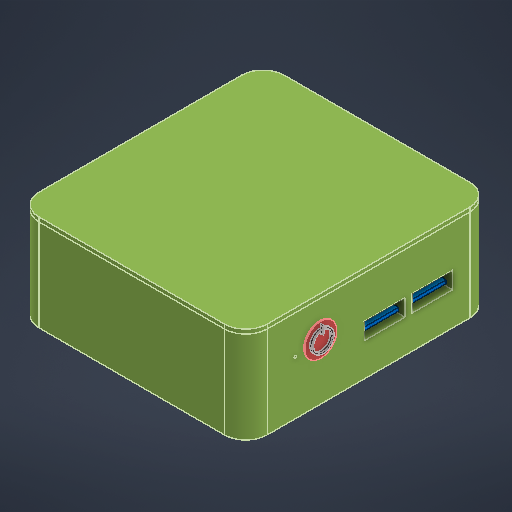
# Autodesk Inventor part: PC
Saved by Autodesk Inventor 2027.1 (Build 311270010, 270A)
## iProperties
Created: 2026-10-10
Part Number: PC
Material: PC/ABS 플라스틱
Document SubType Name: Modeling
Designer: work
Density: 1.1 g/cm^3
Appearance: 올리브 녹색
Author: work
Autodesk Inventor part; units mm, degrees
ref_plane "YZ Plane" through (0, 0, 0) normal (1, 0, 0) x (0, 1, 0)
ref_plane "XZ Plane" through (0, 0, 0) normal (0, 1, 0) x (-1, 0, 0)
sketch "스케치1" plane through (0, 0, 0) normal (0, 1, 0) x (-1, 0, 0)
  line L0 (0, 0) -> (107, 0)
  line L1 (107, 0) -> (107, -115)
  line L2 (107, -115) -> (0, -115)
  line L3 (0, -115) -> (0, 0)
  dimension "d0" = 107
  dimension "d1" = 115
  constraints: 8 end point, 2 parallel, 1 horizontal, 1 perpendicular
  measures "d0" distance of L1.end L2.end
  measures "d1" distance of L0.end L1.end
extrude "돌출1" add sketch "스케치1" along normal blind 45
fillet "모깎기1" radius 10 4 edges at (-107, 22.5, 0) (0, 22.5, 0) (0, 22.5, -115) (-107, 22.5, -115)
sketch "스케치2" plane through (0, 0, -10) normal (1, 0, 0) x (0, 0, -1)
  circle A0 centre (24.6249, 26.5813) radius 7.5
  line L0 (45.4553, 23.4003) -> (86.8672, 23.4003)
  line L1 (86.8672, 23.4003) -> (86.8672, 15.5256)
  line L2 (86.8672, 15.5256) -> (45.4553, 15.5256)
  line L3 (45.4553, 15.5256) -> (45.4553, 23.4003)
  line L4 (64.5413, 23.4003) -> (67.7812, 23.4003)
  line L5 (67.7812, 23.4003) -> (67.7812, 15.5256)
  line L6 (67.7812, 15.5256) -> (64.5413, 15.5256)
  line L7 (64.5413, 15.5256) -> (64.5413, 23.4003)
  point P0 (-10, 0)
  point P1 (66.1613, 23.4003)
  dimension "d5" = 15
  constraints: 16 end point, 4 parallel, 2 horizontal, 2 midpoint, 2 perpendicular, 2 point on line, 1 centre point
  measures "d5" diameter of A0
extrude "돌출2" add sketch "스케치2" along normal blind 0.5 separate body contours A0
extrude "돌출3" cut sketch "스케치2" against normal blind 20 contours L0 L7 L2 L3 | L0 L1 L2 L5 bodies 1
sketch "스케치3" plane through (-20, 0, -10) normal (1, 0, 0) x (0, 0, -1)
  line L0 (64.5413, 15.5256) -> (45.4553, 15.5256) projected
  line L1 (64.5413, 23.4003) -> (64.5413, 15.5256) projected
  line L2 (45.4553, 23.4003) -> (64.5413, 23.4003) projected
  line L3 (45.4553, 15.5256) -> (45.4553, 23.4003) projected
  line L4 (67.7812, 23.4003) -> (86.8672, 23.4003) projected
  line L5 (67.7812, 15.5256) -> (67.7812, 23.4003) projected
  line L6 (86.8672, 15.5256) -> (67.7812, 15.5256) projected
  line L7 (86.8672, 23.4003) -> (86.8672, 15.5256) projected
  line L8 (64.5413, 15.5256) -> (67.7812, 15.5256)
  line L9 (66.1613, 15.5256) -> (66.1613, 23.4003)
  line L10 (46.4553, 19.0256) -> (63.5413, 19.0256)
  line L11 (63.5413, 19.0256) -> (63.5413, 17.5256)
  line L12 (63.5413, 17.5256) -> (46.4553, 17.5256)
  line L13 (46.4553, 17.5256) -> (46.4553, 19.0256)
  line L14 (85.8672, 19.0256) -> (68.7812, 19.0256)
  line L15 (68.7812, 19.0256) -> (68.7812, 17.5256)
  line L16 (68.7812, 17.5256) -> (85.8672, 17.5256)
  line L17 (85.8672, 17.5256) -> (85.8672, 19.0256)
  point P0 (-10, 0)
  point P1 (54.9983, 19.0256)
  point P2 (54.9983, 23.4003)
  point P3 (46.4553, 18.2756)
  point P4 (77.3242, 19.0256)
  point P5 (85.8672, 18.2756)
  dimension "d10" = 1.5
  dimension "d11" = 1
  dimension "d12" = 2
  constraints: 20 end point, 6 symmetric about line, 4 midpoint, 2 horizontal, 2 parallel, 1 perpendicular, 1 vertical, 1 vertical alignment
  measures "d10" distance between parallel lines of L12 L10
  measures "d11" distance from line of L3 point (46.455, 18.276)
  measures "d12" distance between parallel lines of L0 L12
extrude "돌출4" add sketch "스케치3" along normal blind 18 separate body contours L10 L11 L12 L13 | L17 L16 L15 L14
ref_plane "작업 평면1" through (0, 43, 0) normal (0, 1, 0) x (1, 0, 0)
split body "분할1" result two bodies by plane through (0, 43, 0) normal (0, 1, 0) bodies 1 first body at (-35.6667, 44.5, -41.6667)
sketch "스케치4" plane through (0.5, 26.5813, -34.6249) normal (1, 0, 0) x (0, 0, -1)
  circle A0 centre (0, 0) radius 5.177
  circle A1 centre (0, 0) radius 4.3493
  line L0 (0.1162, 6.062) -> (0.1162, 2.6336) construction
  line L1 (-0.2316, 6.062) -> (-0.2316, 2.6336)
  line L2 (0.4641, 2.6336) -> (0.4641, 6.062)
  arc A2 (0.4641, 6.062) -> (-0.2316, 6.062) centre (0.1162, 6.062) ccw
  arc A3 (-0.2316, 2.6336) -> (0.4641, 2.6336) centre (0.1162, 2.6336) ccw
  line L3 (0.1162, 2.6336) -> (0.1162, 6.062) construction
  line L4 (1.081, 2.6336) -> (1.081, 6.062)
  line L5 (-0.8486, 6.062) -> (-0.8486, 2.6336)
  arc A4 (-0.8486, 2.6336) -> (1.081, 2.6336) centre (0.1162, 2.6336) ccw
  arc A5 (1.081, 6.062) -> (-0.8486, 6.062) centre (0.1162, 6.062) ccw
  point P0 (-34.6249, -26.5813)
  point P1 (0.1162, 4.3478)
  point P2 (-0.8486, 4.2657)
  point P3 (-0.8486, 5.107)
  point P4 (1.081, 5.0629)
  point P5 (1.081, 4.2128)
  constraints: 16 end point, 8 point on circle, 8 tangent, 5 centre point, 3 parallel, 2 midpoint, 1 coincident, 1 vertical, 3 other
extrude "돌출5" add sketch "스케치4" along normal blind 1 separate body contours A0 L5 A1 L4 | L2 A1 L1 A0 | A0 L1 A2 L2 | L2 A3 L1 A1
sketch "스케치5" plane through (0, 0, -10) normal (1, 0, 0) x (0, 0, -1)
  circle A0 centre (13.1572, 24.9961) radius 0.621
  point P0 (-10, 0)
  constraints: 1 centre point
extrude "돌출6" cut sketch "스케치5" against normal blind 3 bodies 5
